Autodesk Fusion 360 part; units mm, degrees
(part 2 of 2)
sketch "스케치4" plane through (0, 3, 0) normal (0, 1, 0) x (-1, 0, 0)
  arc A0 (-72, -15) -> (-75, -18) centre (-72, -18) ccw
  line L0 (-72, -15) -> (-58, -15)
  arc A1 (-55, -18) -> (-58, -15) centre (-58, -18) ccw
  line L1 (-55, -18) -> (-55, -32)
  arc A2 (-58, -35) -> (-55, -32) centre (-58, -32) ccw
  line L2 (-58, -35) -> (58, -35)
  arc A3 (55, -32) -> (58, -35) centre (58, -32) ccw
  line L3 (55, -32) -> (55, -18)
  arc A4 (58, -15) -> (55, -18) centre (58, -18) ccw
  line L4 (58, -15) -> (72, -15)
  arc A5 (75, -18) -> (72, -15) centre (72, -18) ccw
  line L5 (75, -18) -> (75, 32)
  arc A6 (75, 32) -> (72, 35) centre (72, 32) ccw
  line L6 (72, 35) -> (-72, 35)
  arc A7 (-72, 35) -> (-75, 32) centre (-72, 32) ccw
  line L7 (-75, 32) -> (-75, -18)
  line L8 (36.5, -10) -> (36.5, 5)
  arc A8 (36.5, 5) -> (23.5, 5) centre (30, 5) ccw
  line L9 (23.5, 5) -> (23.5, -10)
  arc A9 (23.5, -10) -> (36.5, -10) centre (30, -10) ccw
  line L10 (30, -10) -> (30, 5) construction
  line L11 (36.5, -2.5) -> (23.5, -2.5) construction
  dimension "d29" = 6.5
  dimension "d30" = 15
  dimension "d31" = 30
  dimension "d32" = 2.5
  constraint tangent L8 A8
  constraint tangent A8 L9
  constraint parallel L8 L9
  constraint tangent L9 A9
  constraint tangent L8 A9
  constraint parallel L3 L10
  constraint midpoint L8 L11.start
  constraint midpoint L9 L11.end
  measures "d29" radius of A9
  measures "d30" distance of A8.end L9.end
  measures "d31" horizontal distance of origin A8.centre
  measures "d32" distance of origin L11
extrude "돌출5" cut sketch "스케치4" against normal blind 3 contours L8 A8 L9 A9
sketch "스케치5" plane through (0, 3, 0) normal (0, 1, 0) x (-1, 0, 0)
  line L0 (36.5, 5) -> (36.5, -10)
  arc A0 (23.5, -10) -> (36.5, -10) centre (30, -10) ccw
  line L1 (23.5, -10) -> (23.5, 5)
  arc A1 (36.5, 5) -> (23.5, 5) centre (30, 5) ccw
  arc A2 (-72, -15) -> (-75, -18) centre (-72, -18) ccw
  line L2 (-72, -15) -> (-58, -15)
  arc A3 (-55, -18) -> (-58, -15) centre (-58, -18) ccw
  line L3 (-55, -18) -> (-55, -32)
  arc A4 (-58, -35) -> (-55, -32) centre (-58, -32) ccw
  line L4 (-58, -35) -> (58, -35)
  arc A5 (55, -32) -> (58, -35) centre (58, -32) ccw
  line L5 (55, -32) -> (55, -18)
  arc A6 (58, -15) -> (55, -18) centre (58, -18) ccw
  line L6 (58, -15) -> (72, -15)
  arc A7 (75, -18) -> (72, -15) centre (72, -18) ccw
  line L7 (75, -18) -> (75, 32)
  arc A8 (75, 32) -> (72, 35) centre (72, 32) ccw
  line L8 (72, 35) -> (-72, 35)
  arc A9 (-72, 35) -> (-75, 32) centre (-72, 32) ccw
  line L9 (-75, 32) -> (-75, -18)
  circle A10 centre (30.1918, -2.3934) radius 15.6 construction
  line L10 (38.0181, -15.8882) -> (22.3655, 11.1014) construction
  line L11 (38.0732, 11.0693) -> (22.3104, -15.856) construction
  line L12 (45.7918, -2.3934) -> (14.5918, -2.3934) construction
  line L13 (16.3418, -2.3934) -> (16.3418, 12.6066)
  arc A11 (16.3418, 12.6066) -> (12.8418, 12.6066) centre (14.5918, 12.6066) ccw
  line L14 (12.8418, 12.6066) -> (12.8418, -2.3934)
  arc A12 (12.8418, -2.3934) -> (16.3418, -2.3934) centre (14.5918, -2.3934) ccw
  line L15 (14.5918, -2.3934) -> (14.5918, 12.6066) construction
  line L16 (24.1155, 11.1014) -> (24.1155, 26.1014)
  arc A13 (24.1155, 26.1014) -> (20.6155, 26.1014) centre (22.3655, 26.1014) ccw
  line L17 (20.6155, 26.1014) -> (20.6155, 11.1014)
  arc A14 (20.6155, 11.1014) -> (24.1155, 11.1014) centre (22.3655, 11.1014) ccw
  line L18 (22.3655, 11.1014) -> (22.3655, 26.1014) construction
  line L19 (39.8232, 11.0693) -> (39.8232, 26.0693)
  arc A15 (39.8232, 26.0693) -> (36.3232, 26.0693) centre (38.0732, 26.0693) ccw
  line L20 (36.3232, 26.0693) -> (36.3232, 11.0693)
  arc A16 (36.3232, 11.0693) -> (39.8232, 11.0693) centre (38.0732, 11.0693) ccw
  line L21 (38.0732, 11.0693) -> (38.0732, 26.0693) construction
  line L22 (47.5418, -2.3934) -> (47.5418, 12.6066)
  arc A17 (47.5418, 12.6066) -> (44.0418, 12.6066) centre (45.7918, 12.6066) ccw
  line L23 (44.0418, 12.6066) -> (44.0418, -2.3934)
  arc A18 (44.0418, -2.3934) -> (47.5418, -2.3934) centre (45.7918, -2.3934) ccw
  line L24 (45.7918, -2.3934) -> (45.7918, 12.6066) construction
  dimension "d35" = 31.2
  dimension "d36" = 3.5
  dimension "d37" = 3.5
  dimension "d38" = 3.5
  dimension "d39" = 3.5
  constraint coincident A10 L10.start
  constraint coincident A10 L10.end
  constraint perpendicular A10 L10
  constraint coincident A10 L11.start
  constraint coincident A10 L11.end
  constraint perpendicular A10 L11
  constraint coincident A10 L12.start
  constraint coincident A10 L12.end
  constraint perpendicular A10 L12
  constraint tangent L13 A11
  constraint tangent A11 L14
  constraint parallel L13 L14
  constraint tangent L14 A12
  constraint tangent L13 A12
  constraint perpendicular L12 L15
  constraint coincident L12.end A12.centre
  constraint tangent L16 A13
  constraint tangent A13 L17
  constraint parallel L16 L17
  constraint tangent L17 A14
  constraint tangent L16 A14
  constraint vertical L18
  constraint coincident L10.end A14.centre
  constraint tangent L19 A15
  constraint tangent A15 L20
  constraint parallel L19 L20
  constraint tangent L20 A16
  constraint tangent L19 A16
  constraint vertical L21
  constraint coincident L11.start A16.centre
  constraint tangent L22 A17
  constraint tangent A17 L23
  constraint parallel L22 L23
  constraint tangent L23 A18
  constraint tangent L22 A18
  constraint perpendicular L12 L24
  constraint coincident L12.start A18.centre
  measures "d35" diameter of A10
  measures "d36" diameter of A11
  measures "d37" diameter of A13
  measures "d38" diameter of A15
  measures "d39" diameter of A17
extrude "돌출6" cut sketch "스케치5" against normal blind 3 contours L13 A11 L14 A12 | L16 A13 L17 A14 | L19 A15 L20 A16 | L22 A17 L23 A18
sketch "스케치6" plane through (0, 3, 0) normal (0, 1, 0) x (-1, 0, 0)
  arc A0 (-72, -15) -> (-75, -18) centre (-72, -18) ccw
  line L0 (-72, -15) -> (-58, -15)
  arc A1 (-55, -18) -> (-58, -15) centre (-58, -18) ccw
  line L1 (-55, -18) -> (-55, -32)
  arc A2 (-58, -35) -> (-55, -32) centre (-58, -32) ccw
  line L2 (-58, -35) -> (58, -35)
  arc A3 (55, -32) -> (58, -35) centre (58, -32) ccw
  line L3 (55, -32) -> (55, -18)
  arc A4 (58, -15) -> (55, -18) centre (58, -18) ccw
  line L4 (58, -15) -> (72, -15)
  arc A5 (75, -18) -> (72, -15) centre (72, -18) ccw
  line L5 (75, -18) -> (75, 32)
  arc A6 (75, 32) -> (72, 35) centre (72, 32) ccw
  line L6 (72, 35) -> (-72, 35)
  arc A7 (-72, 35) -> (-75, 32) centre (-72, 32) ccw
  line L7 (-75, 32) -> (-75, -18)
  line L8 (36.5, 5) -> (36.5, -10)
  arc A8 (23.5, -10) -> (36.5, -10) centre (30, -10) ccw
  line L9 (23.5, -10) -> (23.5, 5)
  arc A9 (36.5, 5) -> (23.5, 5) centre (30, 5) ccw
  line L10 (16.3418, 12.6066) -> (16.3418, -2.3934)
  arc A10 (12.8418, -2.3934) -> (16.3418, -2.3934) centre (14.5918, -2.3934) ccw
  line L11 (12.8418, -2.3934) -> (12.8418, 12.6066)
  arc A11 (16.3418, 12.6066) -> (12.8418, 12.6066) centre (14.5918, 12.6066) ccw
  line L12 (47.5418, 12.6066) -> (47.5418, -2.3934)
  arc A12 (44.0418, -2.3934) -> (47.5418, -2.3934) centre (45.7918, -2.3934) ccw
  line L13 (44.0418, -2.3934) -> (44.0418, 12.6066)
  arc A13 (47.5418, 12.6066) -> (44.0418, 12.6066) centre (45.7918, 12.6066) ccw
  line L14 (24.1155, 26.1014) -> (24.1155, 11.1014)
  arc A14 (20.6155, 11.1014) -> (24.1155, 11.1014) centre (22.3655, 11.1014) ccw
  line L15 (20.6155, 11.1014) -> (20.6155, 26.1014)
  arc A15 (24.1155, 26.1014) -> (20.6155, 26.1014) centre (22.3655, 26.1014) ccw
  line L16 (39.8232, 26.0693) -> (39.8232, 11.0693)
  arc A16 (36.3232, 11.0693) -> (39.8232, 11.0693) centre (38.0732, 11.0693) ccw
  line L17 (36.3232, 11.0693) -> (36.3232, 26.0693)
  arc A17 (39.8232, 26.0693) -> (36.3232, 26.0693) centre (38.0732, 26.0693) ccw
  circle A18 centre (-30, 5) radius 22.5
  dimension "d42" = 45
  dimension "d43" = 5
  dimension "d44" = 30
  measures "d42" diameter of A18
  measures "d43" vertical distance of origin A18.centre
  measures "d44" horizontal distance of origin A18.centre
extrude "돌출7" cut sketch "스케치6" against normal blind 3 contours A18
sketch "스케치7" plane through (0, 3, 0) normal (0, 1, 0) x (-1, 0, 0)
  circle A0 centre (-30, 5) radius 22.5
  arc A1 (-72, -15) -> (-75, -18) centre (-72, -18) ccw
  line L0 (-72, -15) -> (-58, -15)
  arc A2 (-55, -18) -> (-58, -15) centre (-58, -18) ccw
  line L1 (-55, -18) -> (-55, -32)
  arc A3 (-58, -35) -> (-55, -32) centre (-58, -32) ccw
  line L2 (-58, -35) -> (58, -35)
  arc A4 (55, -32) -> (58, -35) centre (58, -32) ccw
  line L3 (55, -32) -> (55, -18)
  arc A5 (58, -15) -> (55, -18) centre (58, -18) ccw
  line L4 (58, -15) -> (72, -15)
  arc A6 (75, -18) -> (72, -15) centre (72, -18) ccw
  line L5 (75, -18) -> (75, 32)
  arc A7 (75, 32) -> (72, 35) centre (72, 32) ccw
  line L6 (72, 35) -> (-72, 35)
  arc A8 (-72, 35) -> (-75, 32) centre (-72, 32) ccw
  line L7 (-75, 32) -> (-75, -18)
  line L8 (36.5, 5) -> (36.5, -10)
  arc A9 (23.5, -10) -> (36.5, -10) centre (30, -10) ccw
  line L9 (23.5, -10) -> (23.5, 5)
  arc A10 (36.5, 5) -> (23.5, 5) centre (30, 5) ccw
  line L10 (16.3418, 12.6066) -> (16.3418, -2.3934)
  arc A11 (12.8418, -2.3934) -> (16.3418, -2.3934) centre (14.5918, -2.3934) ccw
  line L11 (12.8418, -2.3934) -> (12.8418, 12.6066)
  arc A12 (16.3418, 12.6066) -> (12.8418, 12.6066) centre (14.5918, 12.6066) ccw
  line L12 (47.5418, 12.6066) -> (47.5418, -2.3934)
  arc A13 (44.0418, -2.3934) -> (47.5418, -2.3934) centre (45.7918, -2.3934) ccw
  line L13 (44.0418, -2.3934) -> (44.0418, 12.6066)
  arc A14 (47.5418, 12.6066) -> (44.0418, 12.6066) centre (45.7918, 12.6066) ccw
  line L14 (24.1155, 26.1014) -> (24.1155, 11.1014)
  arc A15 (20.6155, 11.1014) -> (24.1155, 11.1014) centre (22.3655, 11.1014) ccw
  line L15 (20.6155, 11.1014) -> (20.6155, 26.1014)
  arc A16 (24.1155, 26.1014) -> (20.6155, 26.1014) centre (22.3655, 26.1014) ccw
  line L16 (39.8232, 26.0693) -> (39.8232, 11.0693)
  arc A17 (36.3232, 11.0693) -> (39.8232, 11.0693) centre (38.0732, 11.0693) ccw
  line L17 (36.3232, 11.0693) -> (36.3232, 26.0693)
  arc A18 (39.8232, 26.0693) -> (36.3232, 26.0693) centre (38.0732, 26.0693) ccw
  line L18 (53, -32) -> (-53, -32)
  line L19 (-53, -32) -> (-53, -29)
  line L20 (-53, -29) -> (53, -29)
  line L21 (53, -29) -> (53, -32)
  dimension "d47" = 3
  dimension "d48" = 3
  dimension "d49" = 106
  dimension "d50" = 53
  constraint horizontal L18
  constraint vertical L19
  constraint horizontal L20
  constraint vertical L21
  measures "d47" distance of L2 L18
  measures "d48" distance of L18.end L19.end
  measures "d49" distance of L19.end L20.end
  measures "d50" distance of origin L21
extrude "돌출8" cut sketch "스케치7" against normal blind 3 contours L18 L19 L20 L21
sketch "스케치8" plane through (0, 3, 0) normal (0, 1, 0) x (-1, 0, 0)
  line L0 (-53, -32) -> (-53, -29)
  line L1 (-53, -29) -> (53, -29)
  line L2 (53, -29) -> (53, -32)
  line L3 (53, -32) -> (-53, -32)
  circle A0 centre (-30, 5) radius 22.5
  arc A1 (-72, -15) -> (-75, -18) centre (-72, -18) ccw
  line L4 (-72, -15) -> (-58, -15)
  arc A2 (-55, -18) -> (-58, -15) centre (-58, -18) ccw
  line L5 (-55, -18) -> (-55, -32)
  arc A3 (-58, -35) -> (-55, -32) centre (-58, -32) ccw
  line L6 (-58, -35) -> (58, -35)
  arc A4 (55, -32) -> (58, -35) centre (58, -32) ccw
  line L7 (55, -32) -> (55, -18)
  arc A5 (58, -15) -> (55, -18) centre (58, -18) ccw
  line L8 (58, -15) -> (72, -15)
  arc A6 (75, -18) -> (72, -15) centre (72, -18) ccw
  line L9 (75, -18) -> (75, 32)
  arc A7 (75, 32) -> (72, 35) centre (72, 32) ccw
  line L10 (72, 35) -> (-72, 35)
  arc A8 (-72, 35) -> (-75, 32) centre (-72, 32) ccw
  line L11 (-75, 32) -> (-75, -18)
  line L12 (36.5, 5) -> (36.5, -10)
  arc A9 (23.5, -10) -> (36.5, -10) centre (30, -10) ccw
  line L13 (23.5, -10) -> (23.5, 5)
  arc A10 (36.5, 5) -> (23.5, 5) centre (30, 5) ccw
  line L14 (16.3418, 12.6066) -> (16.3418, -2.3934)
  arc A11 (12.8418, -2.3934) -> (16.3418, -2.3934) centre (14.5918, -2.3934) ccw
  line L15 (12.8418, -2.3934) -> (12.8418, 12.6066)
  arc A12 (16.3418, 12.6066) -> (12.8418, 12.6066) centre (14.5918, 12.6066) ccw
  line L16 (47.5418, 12.6066) -> (47.5418, -2.3934)
  arc A13 (44.0418, -2.3934) -> (47.5418, -2.3934) centre (45.7918, -2.3934) ccw
  line L17 (44.0418, -2.3934) -> (44.0418, 12.6066)
  arc A14 (47.5418, 12.6066) -> (44.0418, 12.6066) centre (45.7918, 12.6066) ccw
  line L18 (24.1155, 26.1014) -> (24.1155, 11.1014)
  arc A15 (20.6155, 11.1014) -> (24.1155, 11.1014) centre (22.3655, 11.1014) ccw
  line L19 (20.6155, 11.1014) -> (20.6155, 26.1014)
  arc A16 (24.1155, 26.1014) -> (20.6155, 26.1014) centre (22.3655, 26.1014) ccw
  line L20 (39.8232, 26.0693) -> (39.8232, 11.0693)
  arc A17 (36.3232, 11.0693) -> (39.8232, 11.0693) centre (38.0732, 11.0693) ccw
  line L21 (36.3232, 11.0693) -> (36.3232, 26.0693)
  arc A18 (39.8232, 26.0693) -> (36.3232, 26.0693) centre (38.0732, 26.0693) ccw
  circle A19 centre (36, -25) radius 1.5
  circle A20 centre (-36, -25) radius 1.5
  circle A21 centre (-72, 32) radius 1.5
  circle A22 centre (0, 32) radius 1.5
  circle A23 centre (72, 32) radius 1.5
  dimension "d53" = 3
  dimension "d54" = 3
  dimension "d55" = 3
  dimension "d56" = 3
  dimension "d57" = 3
  dimension "d58" = 25
  dimension "d59" = 25
  dimension "d60" = 72
  dimension "d61" = 36
  constraint concentric A8 A21
  constraint concentric A7 A23
  measures "d53" diameter of A19
  measures "d54" diameter of A20
  measures "d55" diameter of A21
  measures "d56" diameter of A22
  measures "d57" diameter of A23
  measures "d58" vertical distance of origin A20.centre
  measures "d59" vertical distance of origin A19.centre
  measures "d60" distance of A19.centre A20.centre
  measures "d61" horizontal distance of origin A20.centre
extrude "돌출9" cut sketch "스케치8" against normal blind 3 contours A19 | A20 | A21 | A22 | A23
equation "d20 = d19"
equation "d61 = d60 / 2"

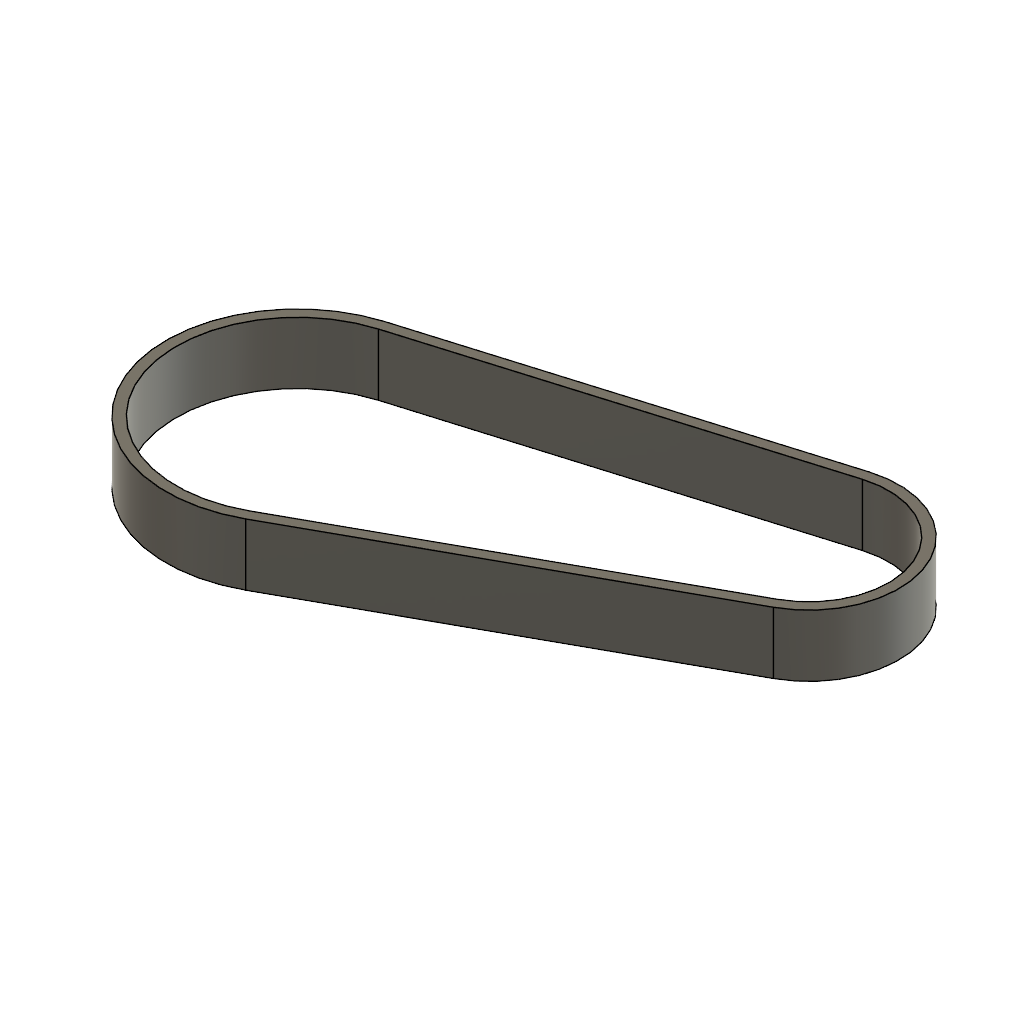
design "풀리벨트"
Autodesk Fusion 360 part; units mm, degrees
sketch "스케치1" plane through (0, 0, 0) normal (0, 1, 0) x (1, 0, 0)
  line L0 (-33.6927, 7.2519) -> (2.459, 18.1213)
  line L1 (-23.8733, -16.1277) -> (9.1978, 2.0764)
  arc A0 (-33.6927, 7.2519) -> (-23.8733, -16.1277) centre (-30.0216, -4.9581) ccw
  arc A1 (9.1978, 2.0764) -> (2.459, 18.1213) centre (4.9784, 9.7419) ccw
  dimension "d1" = 17.5
  dimension "d2" = 25.5
  dimension "d3" = 35
  dimension "d4" = 14.7
  constraint tangent L1 A1
  constraint tangent L0 A0
  constraint tangent L1 A0
  constraint tangent L0 A1
  measures "d1" diameter of A1
  measures "d2" diameter of A0
  measures "d3" horizontal distance of A1.centre A0.centre
  measures "d4" vertical distance of A1.centre A0.centre
extrude "돌출1" add sketch "스케치1" along normal blind 6
sketch "스케치2" plane through (0, 6, 0) normal (0, 1, 0) x (-1, 0, 0)
  arc A0 (33.6927, -7.2519) -> (23.8733, 16.1277) centre (30.0216, 4.9581) ccw
  line L0 (23.8733, 16.1277) -> (-9.1978, -2.0764)
  arc A1 (-9.1978, -2.0764) -> (-2.459, -18.1213) centre (-4.9784, -9.7419) ccw
  line L1 (-2.459, -18.1213) -> (33.6927, -7.2519)
  line L2 (33.4048, -6.2943) -> (-2.7469, -17.1637)
  line L3 (24.3555, 15.2517) -> (-8.7156, -2.9525)
  arc A2 (33.4048, -6.2943) -> (24.3555, 15.2517) centre (30.0216, 4.9581) ccw
  arc A3 (-8.7156, -2.9525) -> (-2.7469, -17.1637) centre (-4.9784, -9.7419) ccw
  dimension "d7" = 23.5
  dimension "d8" = 15.5
  constraint concentric A0 A2
  constraint concentric A1 A3
  constraint tangent L2 A3
  constraint tangent L3 A3
  constraint tangent L2 A2
  constraint tangent L3 A2
  measures "d7" diameter of A2
  measures "d8" diameter of A3
extrude "돌출2" cut sketch "스케치2" against normal blind 6 contours L2 L3 A2 A3

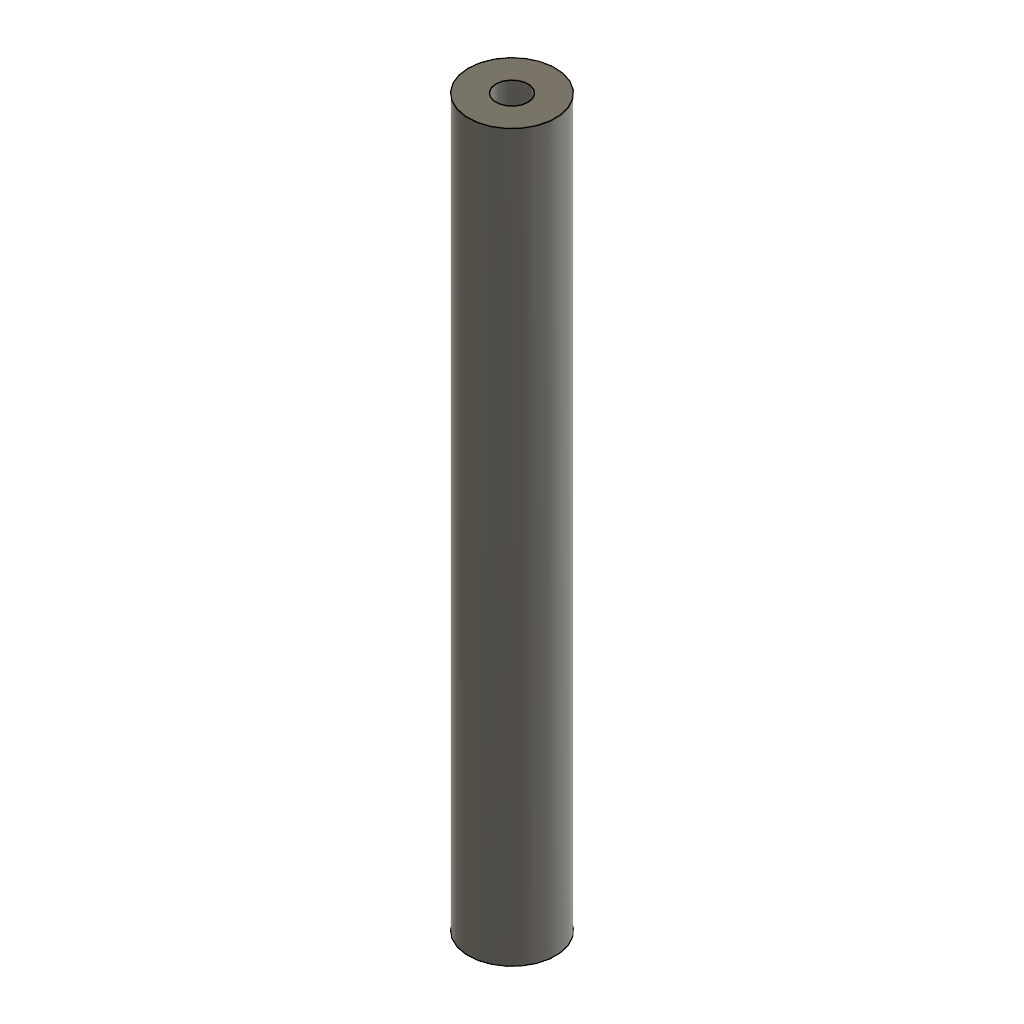
design "서포트너트"
Autodesk Fusion 360 part; units mm, degrees
sketch "스케치1" plane through (0, 0, 0) normal (0, 1, 0) x (1, 0, 0)
  circle A0 centre (0, 0) radius 3
  dimension "d1" = 6
  constraint coincident A0.centre origin
  measures "d1" diameter of A0
extrude "돌출1" add sketch "스케치1" along normal blind 50
sketch "스케치2" plane through (0, 0, 0) normal (0, -1, 0) x (1, 0, 0)
  circle A0 centre (0, 0) radius 3
  circle A1 centre (0, 0) radius 1.1
  dimension "d4" = 2.2
  constraint coincident A0.centre A1.centre
  measures "d4" diameter of A1
extrude "돌출2" cut sketch "스케치2" against normal blind 10 contours A1
sketch "스케치3" plane through (0, 50, 0) normal (0, 1, 0) x (-1, 0, 0)
  circle A0 centre (0, 0) radius 3
  circle A1 centre (0, 0) radius 1.1
  dimension "d7" = 2.2
  constraint coincident A0.centre A1.centre
  measures "d7" diameter of A1
extrude "돌출3" cut sketch "스케치3" against normal blind 10 contours A1

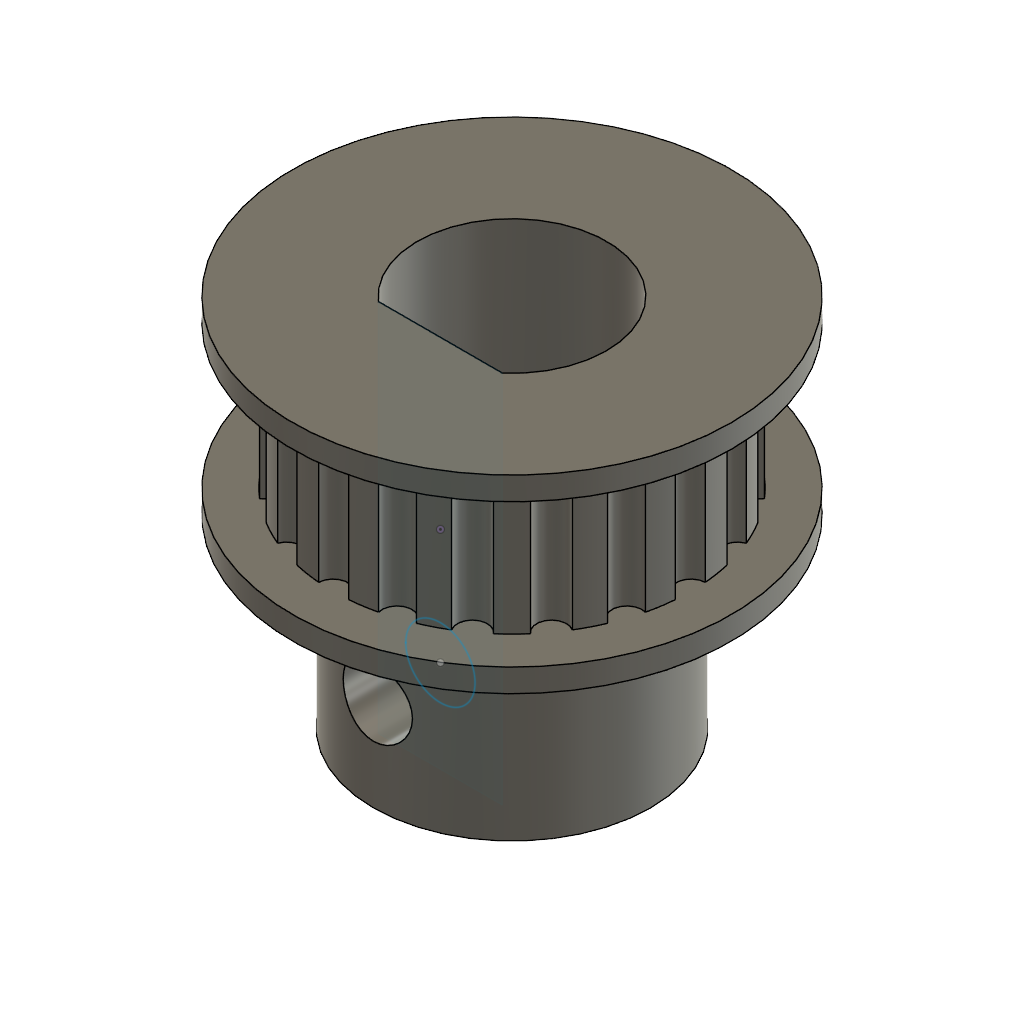
design "축풀리"
Autodesk Fusion 360 part; units mm, degrees
sketch "스케치1" plane through (0, 0, 0) normal (0, 1, 0) x (1, 0, 0)
  circle A0 centre (0, 0) radius 7.75
  dimension "d1" = 15.5
  constraint coincident A0.centre origin
  measures "d1" diameter of A0
extrude "돌출1" add sketch "스케치1" along normal blind 6.2
sketch "스케치2" plane through (0, 6.2, 0) normal (0, 1, 0) x (-1, 0, 0)
  circle A0 centre (0, 0) radius 7.75
  circle A1 centre (-7.75, 0) radius 0.65
  circle A2 centre (-7.3707, -2.3949) radius 0.65
  circle A3 centre (-6.2699, -4.5553) radius 0.65
  circle A4 centre (-4.5553, -6.2699) radius 0.65
  circle A5 centre (-2.3949, -7.3707) radius 0.65
  circle A6 centre (0, -7.75) radius 0.65
  circle A7 centre (2.3949, -7.3707) radius 0.65
  circle A8 centre (4.5553, -6.2699) radius 0.65
  circle A9 centre (6.2699, -4.5553) radius 0.65
  circle A10 centre (7.3707, -2.3949) radius 0.65
  circle A11 centre (7.75, 0) radius 0.65
  circle A12 centre (7.3707, 2.3949) radius 0.65
  circle A13 centre (6.2699, 4.5553) radius 0.65
  circle A14 centre (4.5553, 6.2699) radius 0.65
  circle A15 centre (2.3949, 7.3707) radius 0.65
  circle A16 centre (0, 7.75) radius 0.65
  circle A17 centre (-2.3949, 7.3707) radius 0.65
  circle A18 centre (-4.5553, 6.2699) radius 0.65
  circle A19 centre (-6.2699, 4.5553) radius 0.65
  circle A20 centre (-7.3707, 2.3949) radius 0.65
  dimension "d4" = 1.3
  dimension "d6" = 360
  constraint coincident A0 A1.centre
  measures "d4" diameter of A1
extrude "돌출2" cut sketch "스케치2" against normal blind 6.2 contours A0 A11 | A0 A12 | A0 A10 | A0 A13 | A0 A9 | A0 A14 | A0 A8 | A0 A15 | A0 A7 | A0 A16 | A0 A6 | A0 A17 | A0 A5 | A0 A18 | A0 A4 | A0 A19 | A0 A3 | A0 A20 | A0 A2 | A0 A1 picked at (7.5465, 0.1494) picked at (7.1584, 2.3425) picked at (7.1584, -2.3425) picked at (6.0842, 4.4399) picked at (6.0842, -4.4399) picked at (4.4399, 6.0842) picked at (4.4399, -6.0842) picked at (2.3125, 7.1681) picked at (2.3425, -7.1584) picked at (0.0158, 7.5319) picked at (-0.0158, -7.5319) picked at (-2.3404, 7.1589) picked at (-2.3404, -7.1589) picked at (-4.4148, 6.1023) picked at (-4.4148, -6.1023) picked at (-6.0865, 4.4363) picked at (-6.0865, -4.4363) picked at (-7.1608, 2.3336) picked at (-7.1608, -2.3336) picked at (-7.5313, 0)
sketch "스케치3" plane through (0, 6.2, 0) normal (0, 1, 0) x (-1, 0, 0)
  arc A0 (6.6296, -4.0139) -> (5.8661, -5.0647) centre (6.2699, -4.5553) ccw
  arc A1 (6.6296, -4.0139) -> (7.1441, -3.0041) centre (0, 0) ccw
  arc A2 (7.5454, -1.7688) -> (7.1441, -3.0041) centre (7.3707, -2.3949) ccw
  arc A3 (7.5454, -1.7688) -> (7.7227, -0.6494) centre (0, 0) ccw
  arc A4 (7.7227, 0.6494) -> (7.7227, -0.6494) centre (7.75, 0) ccw
  arc A5 (7.7227, 0.6494) -> (7.5454, 1.7688) centre (0, 0) ccw
  arc A6 (7.1441, 3.0041) -> (7.5454, 1.7688) centre (7.3707, 2.3949) ccw
  arc A7 (7.1441, 3.0041) -> (6.6296, 4.0139) centre (0, 0) ccw
  arc A8 (5.8661, 5.0647) -> (6.6296, 4.0139) centre (6.2699, 4.5553) ccw
  arc A9 (5.8661, 5.0647) -> (5.0647, 5.8661) centre (0, 0) ccw
  arc A10 (4.0139, 6.6296) -> (5.0647, 5.8661) centre (4.5553, 6.2699) ccw
  arc A11 (4.0139, 6.6296) -> (3.0041, 7.1441) centre (0, 0) ccw
  arc A12 (1.7688, 7.5454) -> (3.0041, 7.1441) centre (2.3949, 7.3707) ccw
  arc A13 (1.7688, 7.5454) -> (0.6494, 7.7227) centre (0, 0) ccw
  arc A14 (-0.6494, 7.7227) -> (0.6494, 7.7227) centre (0, 7.75) ccw
  arc A15 (-0.6494, 7.7227) -> (-1.7688, 7.5454) centre (0, 0) ccw
  arc A16 (-3.0041, 7.1441) -> (-1.7688, 7.5454) centre (-2.3949, 7.3707) ccw
  arc A17 (-3.0041, 7.1441) -> (-4.0139, 6.6296) centre (0, 0) ccw
  arc A18 (-5.0647, 5.8661) -> (-4.0139, 6.6296) centre (-4.5553, 6.2699) ccw
  arc A19 (-5.0647, 5.8661) -> (-5.8661, 5.0647) centre (0, 0) ccw
  arc A20 (-6.6296, 4.0139) -> (-5.8661, 5.0647) centre (-6.2699, 4.5553) ccw
  arc A21 (-6.6296, 4.0139) -> (-7.1441, 3.0041) centre (0, 0) ccw
  arc A22 (-7.5454, 1.7688) -> (-7.1441, 3.0041) centre (-7.3707, 2.3949) ccw
  arc A23 (-7.5454, 1.7688) -> (-7.7227, 0.6494) centre (0, 0) ccw
  arc A24 (-7.7227, -0.6494) -> (-7.7227, 0.6494) centre (-7.75, 0) ccw
  arc A25 (-7.7227, -0.6494) -> (-7.5454, -1.7688) centre (0, 0) ccw
  arc A26 (-7.1441, -3.0041) -> (-7.5454, -1.7688) centre (-7.3707, -2.3949) ccw
  arc A27 (-7.1441, -3.0041) -> (-6.6296, -4.0139) centre (0, 0) ccw
  arc A28 (-5.8661, -5.0647) -> (-6.6296, -4.0139) centre (-6.2699, -4.5553) ccw
  arc A29 (-5.8661, -5.0647) -> (-5.0647, -5.8661) centre (0, 0) ccw
  arc A30 (-4.0139, -6.6296) -> (-5.0647, -5.8661) centre (-4.5553, -6.2699) ccw
  arc A31 (-4.0139, -6.6296) -> (-3.0041, -7.1441) centre (0, 0) ccw
  arc A32 (-1.7688, -7.5454) -> (-3.0041, -7.1441) centre (-2.3949, -7.3707) ccw
  arc A33 (-1.7688, -7.5454) -> (-0.6494, -7.7227) centre (0, 0) ccw
  arc A34 (0.6494, -7.7227) -> (-0.6494, -7.7227) centre (0, -7.75) ccw
  arc A35 (0.6494, -7.7227) -> (1.7688, -7.5454) centre (0, 0) ccw
  arc A36 (3.0041, -7.1441) -> (1.7688, -7.5454) centre (2.3949, -7.3707) ccw
  arc A37 (3.0041, -7.1441) -> (4.0139, -6.6296) centre (0, 0) ccw
  arc A38 (5.0647, -5.8661) -> (4.0139, -6.6296) centre (4.5553, -6.2699) ccw
  arc A39 (5.0647, -5.8661) -> (5.8661, -5.0647) centre (0, 0) ccw
  circle A40 centre (0, 0) radius 9.5
  dimension "d9" = 19
  constraint coincident A1.centre A3.centre
  measures "d9" diameter of A40
extrude "돌출3" add sketch "스케치3" along normal blind 1 contours A0 A1 A2 A3 A4 A5 A6 A7 A8 A9 A10 A11 A12 A13 A14 A15 A16 A17 A18 A19 A20 A21 A22 A23 A24 A25 A26 A27 A28 A29 A30 A31 A32 A33 A34 A35 A36 A37 A38 A39 | A40
sketch "스케치4" plane through (0, 0, 0) normal (0, -1, 0) x (1, 0, 0)
  arc A0 (-5.8661, -5.0647) -> (-6.6296, -4.0139) centre (-6.2699, -4.5553) ccw
  arc A1 (-5.8661, -5.0647) -> (-5.0647, -5.8661) centre (0, 0) ccw
  arc A2 (-4.0139, -6.6296) -> (-5.0647, -5.8661) centre (-4.5553, -6.2699) ccw
  arc A3 (-4.0139, -6.6296) -> (-3.0041, -7.1441) centre (0, 0) ccw
  arc A4 (-1.7688, -7.5454) -> (-3.0041, -7.1441) centre (-2.3949, -7.3707) ccw
  arc A5 (-1.7688, -7.5454) -> (-0.6494, -7.7227) centre (0, 0) ccw
  arc A6 (0.6494, -7.7227) -> (-0.6494, -7.7227) centre (0, -7.75) ccw
  arc A7 (0.6494, -7.7227) -> (1.7688, -7.5454) centre (0, 0) ccw
  arc A8 (3.0041, -7.1441) -> (1.7688, -7.5454) centre (2.3949, -7.3707) ccw
  arc A9 (3.0041, -7.1441) -> (4.0139, -6.6296) centre (0, 0) ccw
  arc A10 (5.0647, -5.8661) -> (4.0139, -6.6296) centre (4.5553, -6.2699) ccw
  arc A11 (5.0647, -5.8661) -> (5.8661, -5.0647) centre (0, 0) ccw
  arc A12 (6.6296, -4.0139) -> (5.8661, -5.0647) centre (6.2699, -4.5553) ccw
  arc A13 (6.6296, -4.0139) -> (7.1441, -3.0041) centre (0, 0) ccw
  arc A14 (7.5454, -1.7688) -> (7.1441, -3.0041) centre (7.3707, -2.3949) ccw
  arc A15 (7.5454, -1.7688) -> (7.7227, -0.6494) centre (0, 0) ccw
  arc A16 (7.7227, 0.6494) -> (7.7227, -0.6494) centre (7.75, 0) ccw
  arc A17 (7.7227, 0.6494) -> (7.5454, 1.7688) centre (0, 0) ccw
  arc A18 (7.1441, 3.0041) -> (7.5454, 1.7688) centre (7.3707, 2.3949) ccw
  arc A19 (7.1441, 3.0041) -> (6.6296, 4.0139) centre (0, 0) ccw
  arc A20 (5.8661, 5.0647) -> (6.6296, 4.0139) centre (6.2699, 4.5553) ccw
  arc A21 (5.8661, 5.0647) -> (5.0647, 5.8661) centre (0, 0) ccw
  arc A22 (4.0139, 6.6296) -> (5.0647, 5.8661) centre (4.5553, 6.2699) ccw
  arc A23 (4.0139, 6.6296) -> (3.0041, 7.1441) centre (0, 0) ccw
  arc A24 (1.7688, 7.5454) -> (3.0041, 7.1441) centre (2.3949, 7.3707) ccw
  arc A25 (1.7688, 7.5454) -> (0.6494, 7.7227) centre (0, 0) ccw
  arc A26 (-0.6494, 7.7227) -> (0.6494, 7.7227) centre (0, 7.75) ccw
  arc A27 (-0.6494, 7.7227) -> (-1.7688, 7.5454) centre (0, 0) ccw
  arc A28 (-3.0041, 7.1441) -> (-1.7688, 7.5454) centre (-2.3949, 7.3707) ccw
  arc A29 (-3.0041, 7.1441) -> (-4.0139, 6.6296) centre (0, 0) ccw
  arc A30 (-5.0647, 5.8661) -> (-4.0139, 6.6296) centre (-4.5553, 6.2699) ccw
  arc A31 (-5.0647, 5.8661) -> (-5.8661, 5.0647) centre (0, 0) ccw
  arc A32 (-6.6296, 4.0139) -> (-5.8661, 5.0647) centre (-6.2699, 4.5553) ccw
  arc A33 (-6.6296, 4.0139) -> (-7.1441, 3.0041) centre (0, 0) ccw
  arc A34 (-7.5454, 1.7688) -> (-7.1441, 3.0041) centre (-7.3707, 2.3949) ccw
  arc A35 (-7.5454, 1.7688) -> (-7.7227, 0.6494) centre (0, 0) ccw
  arc A36 (-7.7227, -0.6494) -> (-7.7227, 0.6494) centre (-7.75, 0) ccw
  arc A37 (-7.7227, -0.6494) -> (-7.5454, -1.7688) centre (0, 0) ccw
  arc A38 (-7.1441, -3.0041) -> (-7.5454, -1.7688) centre (-7.3707, -2.3949) ccw
  arc A39 (-7.1441, -3.0041) -> (-6.6296, -4.0139) centre (0, 0) ccw
  circle A40 centre (0, 0) radius 9.5
  dimension "d12" = 19
  constraint concentric A1 A40
  measures "d12" diameter of A40
extrude "돌출4" add sketch "스케치4" along normal blind 1 contours A0 A1 A2 A3 A4 A5 A6 A7 A8 A9 A10 A11 A12 A13 A14 A15 A16 A17 A18 A19 A20 A21 A22 A23 A24 A25 A26 A27 A28 A29 A30 A31 A32 A33 A34 A35 A36 A37 A38 A39 | A40
sketch "스케치5" plane through (0, -1, 0) normal (0, -1, 0) x (1, 0, 0)
  circle A0 centre (0, 0) radius 9.5
  circle A1 centre (0, 0) radius 6
  dimension "d15" = 12
  constraint coincident A0.centre A1.centre
  measures "d15" diameter of A1
extrude "돌출5" add sketch "스케치5" along normal blind 8 contours A1
sketch "스케치6" plane through (0, -9, 0) normal (0, -1, 0) x (1, 0, 0)
  circle A0 centre (0, 0) radius 6
  line L0 (-2.6833, 3.1) -> (2.6833, 3.1)
  arc A1 (-2.6833, 3.1) -> (2.6833, 3.1) centre (0, 0) ccw
  dimension "d18" = 8.2
  dimension "d19" = 3.1
  constraint concentric A0 A1
  constraint horizontal L0
  measures "d18" diameter of A1
  measures "d19" distance of A0.centre L0
extrude "돌출6" cut sketch "스케치6" against normal blind 16.2 contours L0 A1
sketch "스케치7" plane through (0, 0, 3.1) normal (0, 0, -1) x (-1, 0, 0)
  line L0 (-2.6833, -9) -> (2.6833, -9)
  line L1 (2.6833, -9) -> (2.6833, 7.2)
  line L2 (2.6833, 7.2) -> (-2.6833, 7.2)
  line L3 (-2.6833, 7.2) -> (-2.6833, -9)
  circle A0 centre (0, -5) radius 1.5
  dimension "d22" = 3
  dimension "d23" = 5
  measures "d22" diameter of A0
  measures "d23" distance of origin A0.centre
extrude "돌출7" cut sketch "스케치7" against normal blind 3 contours A0
extrude "돌출8" cut sketch "스케치7" along normal blind 9.1 contours A0

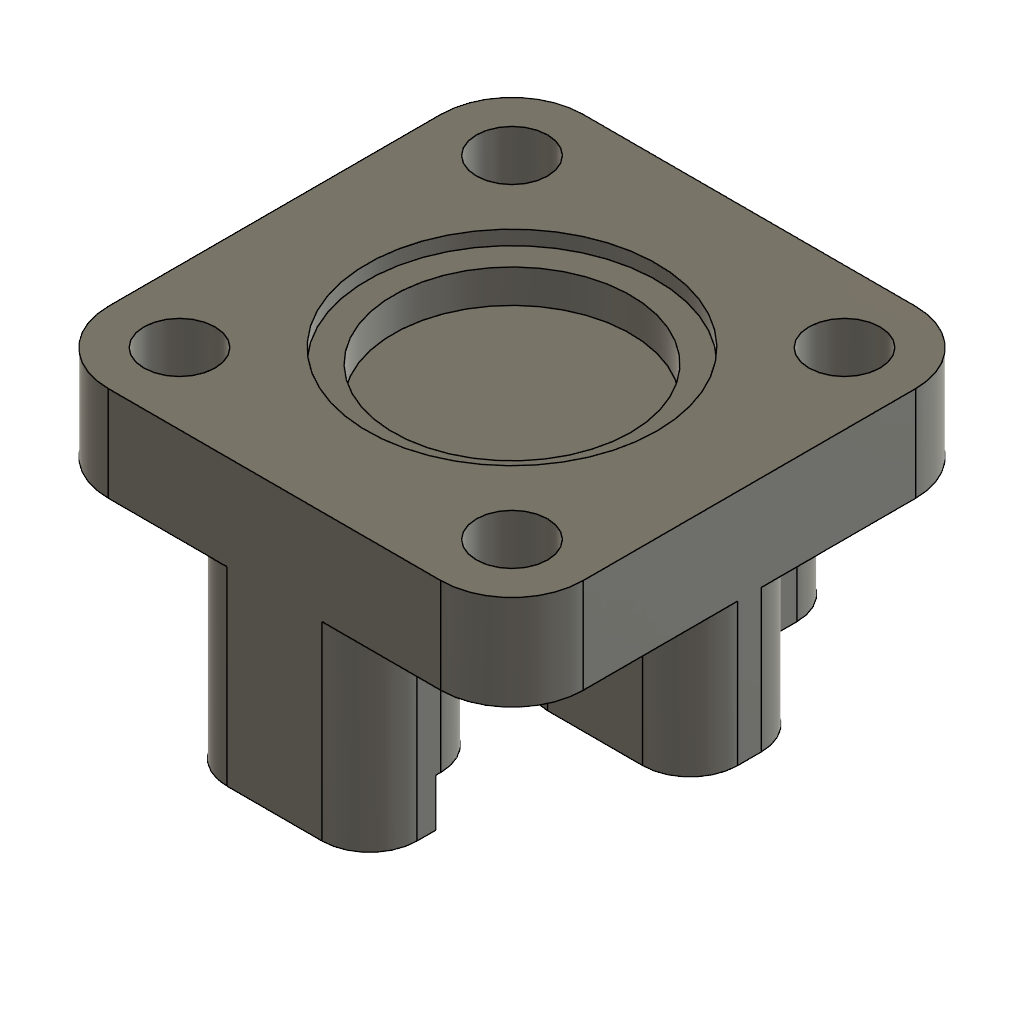
design "베어링커버"
Autodesk Fusion 360 part; units mm, degrees
sketch "스케치1" plane through (0, 0, 0) normal (0, 1, 0) x (1, 0, 0)
  line L0 (-7, 10) -> (7, 10)
  line L1 (10, 7) -> (10, -7)
  line L2 (7, -10) -> (-7, -10)
  line L3 (-10, -7) -> (-10, 7)
  line L4 (0, 10) -> (0, -10) construction
  arc A0 (-7, 10) -> (-10, 7) centre (-7, 7) ccw
  arc A1 (10, 7) -> (7, 10) centre (7, 7) ccw
  arc A2 (7, -10) -> (10, -7) centre (7, -7) ccw
  arc A3 (-10, -7) -> (-7, -10) centre (-7, -7) ccw
  point P0 (-10, 10)
  point P1 (10, 10)
  point P2 (10, -10)
  dimension "d1" = 20
  dimension "d2" = 20
  dimension "d3" = 3
  constraint horizontal L0
  constraint vertical L1
  constraint horizontal L2
  constraint vertical L3
  constraint midpoint origin L4
  constraint coincident L0 L4.start
  constraint coincident P0 L3
  constraint coincident P0 L0
  constraint tangent L3 A0
  constraint tangent L0 A0
  constraint coincident P1 L0
  constraint coincident P1 L1
  constraint tangent L0 A1
  constraint tangent L1 A1
  constraint equal A0 A1
  constraint coincident L2 L4.end
  constraint coincident P2 L1
  constraint coincident P2 L2
  constraint tangent L1 A2
  constraint tangent L2 A2
  constraint equal A0 A2
  constraint tangent L2 A3
  constraint tangent L3 A3
  constraint equal A0 A3
  measures "d1" distance of P0 P1
  measures "d2" distance of P1 P2
  measures "d3" radius of A0
extrude "돌출1" add sketch "스케치1" along normal blind 4
sketch "스케치2" plane through (0, 4, 0) normal (0, 1, 0) x (-1, 0, 0)
  arc A0 (7, -10) -> (10, -7) centre (7, -7) ccw
  line L0 (10, -7) -> (10, 7)
  arc A1 (10, 7) -> (7, 10) centre (7, 7) ccw
  line L1 (7, 10) -> (-7, 10)
  arc A2 (-7, 10) -> (-10, 7) centre (-7, 7) ccw
  line L2 (-10, 7) -> (-10, -7)
  arc A3 (-10, -7) -> (-7, -10) centre (-7, -7) ccw
  line L3 (-7, -10) -> (7, -10)
  circle A4 centre (0, 0) radius 6.1
  circle A5 centre (0, 0) radius 5
  circle A6 centre (7, -7) radius 1.5
  circle A7 centre (-7, -7) radius 1.5
  circle A8 centre (-7, 7) radius 1.5
  circle A9 centre (7, 7) radius 1.5
  dimension "d6" = 12.2
  dimension "d7" = 10
  dimension "d12" = 3
  dimension "d13" = 3
  dimension "d14" = 3
  dimension "d15" = 3
  constraint coincident A4.centre A5.centre
  constraint concentric A4 A5
  constraint concentric A0 A6
  constraint concentric A3 A7
  constraint concentric A2 A8
  constraint concentric A1 A9
  measures "d6" diameter of A4
  measures "d7" diameter of A5
  measures "d12" diameter of A6
  measures "d13" diameter of A7
  measures "d14" diameter of A8
  measures "d15" diameter of A9
extrude "돌출2" cut sketch "스케치2" against normal blind 2 contours A5
extrude "돌출3" cut sketch "스케치2" against normal blind 0.6 contours A4
extrude "돌출4" cut sketch "스케치2" against normal blind 4 contours A6 | A7 | A8 | A9
sketch "스케치3" plane through (0, 0, 0) normal (0, -1, 0) x (1, 0, 0)
  circle A0 centre (7, 7) radius 1.5
  circle A1 centre (7, -7) radius 1.5
  circle A2 centre (-7, 7) radius 1.5
  circle A3 centre (-7, -7) radius 1.5
  arc A4 (-10, -7) -> (-7, -10) centre (-7, -7) ccw
  line L0 (-7, -10) -> (7, -10)
  arc A5 (7, -10) -> (10, -7) centre (7, -7) ccw
  line L1 (10, -7) -> (10, 7)
  arc A6 (10, 7) -> (7, 10) centre (7, 7) ccw
  line L2 (7, 10) -> (-7, 10)
  arc A7 (-7, 10) -> (-10, 7) centre (-7, 7) ccw
  line L3 (-10, 7) -> (-10, -7)
  line L4 (-2, 10) -> (2, 10)
  line L5 (4, 8) -> (4, 7)
  line L6 (2, 5) -> (-2, 5)
  line L7 (-4, 7) -> (-4, 8)
  line L8 (0, 10) -> (0, -10) construction
  line L9 (-10, 0) -> (10, 0) construction
  arc A8 (-2, 10) -> (-4, 8) centre (-2, 8) ccw
  arc A9 (-4, 7) -> (-2, 5) centre (-2, 7) ccw
  arc A10 (2, 5) -> (4, 7) centre (2, 7) ccw
  arc A11 (4, 8) -> (2, 10) centre (2, 8) ccw
  line L10 (4, -8) -> (4, -7)
  arc A12 (2, -10) -> (4, -8) centre (2, -8) ccw
  line L11 (-2, -10) -> (2, -10)
  arc A13 (-4, -8) -> (-2, -10) centre (-2, -8) ccw
  line L12 (-4, -7) -> (-4, -8)
  arc A14 (-2, -5) -> (-4, -7) centre (-2, -7) ccw
  line L13 (2, -5) -> (-2, -5)
  arc A15 (4, -7) -> (2, -5) centre (2, -7) ccw
  line L14 (-4, 7.2) -> (4, 7.2)
  line L15 (-4, -7.2) -> (4, -7.2)
  line L16 (4, 2.5) -> (8, 2.5)
  line L17 (10, 0.5) -> (10, -0.5)
  line L18 (8, -2.5) -> (4, -2.5)
  line L19 (2, -0.5) -> (2, 0.5)
  circle A16 centre (6, 0) radius 1.1
  arc A17 (4, 2.5) -> (2, 0.5) centre (4, 0.5) ccw
  arc A18 (10, 0.5) -> (8, 2.5) centre (8, 0.5) ccw
  arc A19 (8, -2.5) -> (10, -0.5) centre (8, -0.5) ccw
  arc A20 (2, -0.5) -> (4, -2.5) centre (4, -0.5) ccw
  point P0 (-4, 10)
  point P1 (4, 10)
  point P2 (-4, 5)
  point P3 (2, 2.5)
  point P4 (10, 2.5)
  point P5 (10, -2.5)
  dimension "d18" = 8
  dimension "d19" = 5
  dimension "d20" = 2
  dimension "d21" = 2.8
  dimension "d22" = 5
  dimension "d23" = 8
  dimension "d24" = 2.2
  dimension "d25" = 4
  dimension "d26" = 2
  constraint horizontal L4
  constraint vertical L5
  constraint horizontal L6
  constraint vertical L7
  constraint coincident L2 P0
  constraint midpoint L2 L8.start
  constraint midpoint L0 L8.end
  constraint midpoint L3 L9.start
  constraint midpoint L1 L9.end
  constraint coincident L4 L8.start
  constraint coincident P0 L7
  constraint tangent L7 A8
  constraint tangent L4 A8
  constraint coincident P2 L6
  constraint coincident P2 L7
  constraint tangent L6 A9
  constraint tangent L7 A9
  constraint equal A8 A9
  constraint tangent L5 A10
  constraint tangent L6 A10
  constraint equal A8 A10
  constraint coincident P1 L4
  constraint coincident P1 L5
  constraint tangent L4 A11
  constraint tangent L5 A11
  constraint equal A8 A11
  constraint symmetric L9 L7.end A13.start
  constraint symmetric L9 L4.start L11.start
  constraint symmetric L9 A8 A13
  constraint symmetric L9 L6.end A14.start
  constraint symmetric L9 L7.start L12.start
  constraint symmetric L9 A9 A14
  constraint symmetric L9 L5.end L10.end
  constraint symmetric L9 L6.start L13.start
  constraint symmetric L9 A10 A15
  constraint symmetric L9 L4.end A12.start
  constraint symmetric L9 L5.start L10.start
  constraint symmetric L9 A11 A12
  constraint coincident L7 L14.start
  constraint coincident L5 L14.end
  constraint parallel L4 L14
  constraint symmetric L9 L14.start L15.start
  constraint symmetric L9 L14.end L15.end
  constraint horizontal L16
  constraint vertical L17
  constraint horizontal L18
  constraint vertical L19
  constraint coincident L1 P5
  constraint coincident L9 A16.centre
  constraint coincident P3 L16
  constraint coincident P3 L19
  constraint tangent L16 A17
  constraint tangent L19 A17
  constraint coincident L9.end L17
  constraint coincident P4 L16
  constraint coincident P4 L17
  constraint tangent L16 A18
  constraint tangent L17 A18
  constraint equal A17 A18
  constraint coincident P5 L18
  constraint tangent L17 A19
  constraint tangent L18 A19
  constraint equal A17 A19
  constraint tangent L18 A20
  constraint tangent L19 A20
  constraint equal A17 A20
  measures "d18" distance of P0 P1
  measures "d19" distance of P0 P2
  measures "d20" radius of A8
  measures "d21" distance of L4 L14
  measures "d22" distance of P4 P5
  measures "d23" distance of P3 P4
  measures "d24" diameter of A16
  measures "d25" distance of L17 A16.centre
  measures "d26" radius of A17
extrude "돌출5" add sketch "스케치3" along normal blind 8 contours L0 L10 A12 L11 A13 L12 L15 | L2 L4 L5 L7 A8 A11 L14
extrude "돌출6" add sketch "스케치3" along normal blind 6 contours L10 L12 A14 L13 A15 L15 | L5 L6 L7 A9 A10 L14 | L1 L16 L17 L18 L19 A17 A18 A19 A20
